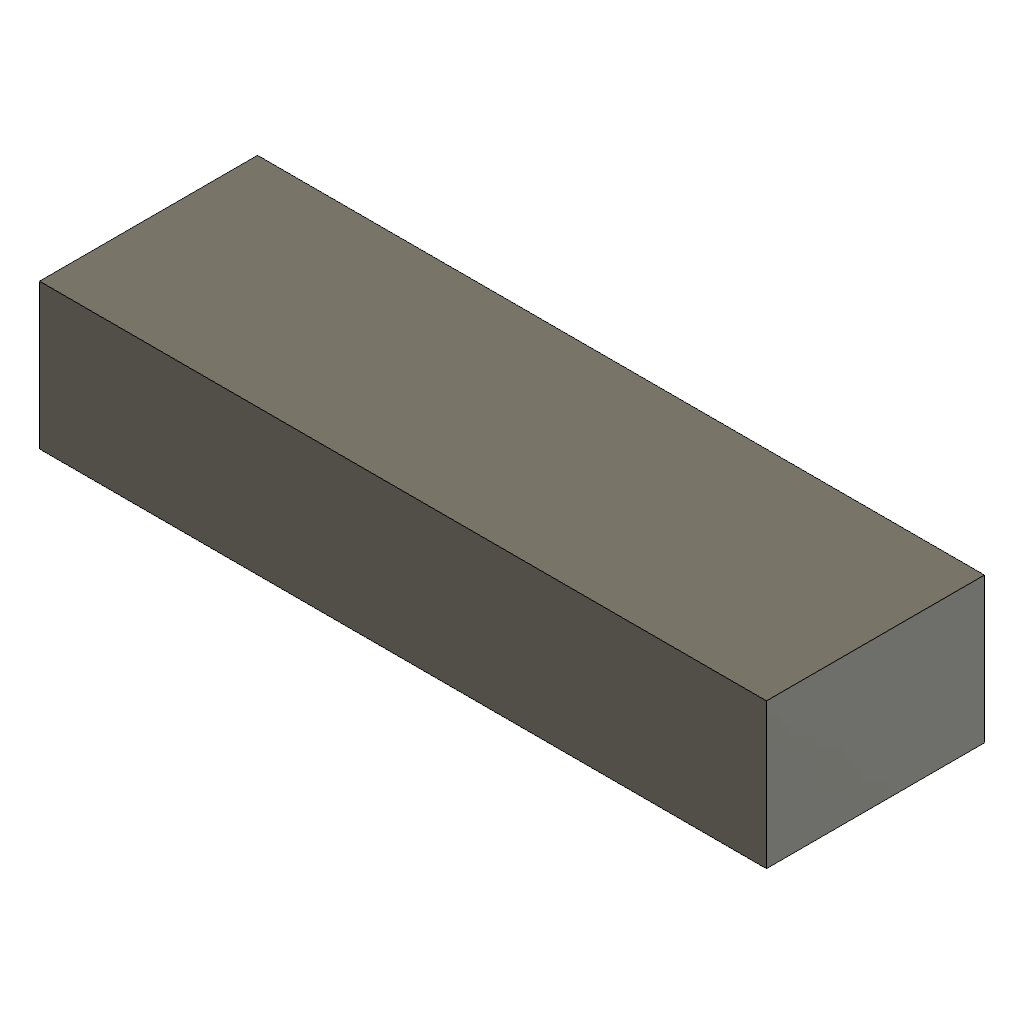
intersect (Autodesk Fusion 360 design; units mm, degrees)
part number: 2026-10-20-22-15-07-113
Autodesk Fusion 360 part; units mm, degrees
sketch "SweepTargetSection" plane through (0, 0, 0) normal (0, 0, 1) x (1, 0, 0)
  line L0 (-10, -10) -> (20, -10)
  line L1 (20, -10) -> (20, 10)
  line L2 (20, 10) -> (-10, 10)
  line L3 (-10, 10) -> (-10, -10)
extrude "StudySweepTargetExtrude" add sketch "SweepTargetSection" along normal mid plane 20
sketch "SweepSection" plane through (0, 0, 0) normal (1, 0, 0) x (0, 0, -1)
  line L0 (-3, -2) -> (3, -2)
  line L1 (3, -2) -> (3, 2)
  line L2 (3, 2) -> (-3, 2)
  line L3 (-3, 2) -> (-3, -2)
sketch "SweepPath" plane through (0, 0, 0) normal (0, 0, 1) x (1, 0, 0)
  line L0 (0, 0) -> (50, 0)
sweep "ProbeSweepOperation" cut profiles "SweepSection" path "SweepPath" along L0 section 1 keep common part
named bodies: "StudySweepTarget"
